Autodesk Fusion 360 part; units mm, degrees
(part 10 of 10)
equation "d2179 = abs(2 * panelWidth - mountInset)"
equation "d2180 = abs(2 * panelHeight - mountInset)"
equation "d2182 = hookClearance - seatThickness"
equation "d2184 = abs(2 * panelWidth - mountInset)"
equation "d2185 = abs(2 * panelHeight - mountInset)"
equation "d2186 = screwClearance"
equation "d2187 = frameZ"
equation "d2189 = -capThickness - 3 mm"
equation "d2191 = abs(2 * panelWidth - mountInset)"
equation "d2192 = abs(2 * panelHeight - mountInset)"
equation "d2196 = -capThickness"
equation "d2198 = abs(2 * panelWidth - mountInset)"
equation "d2199 = abs(2 * panelHeight - mountInset)"
equation "d2201 = frameZ + capThickness + 5 mm"
equation "d2203 = frameZ + profileLip"
equation "d2205 = abs(2 * panelWidth - mountInset - nutWidth / 2)"
equation "d2206 = abs(2 * panelHeight - mountInset - nutLength / 2)"
equation "d2207 = nutWidth"
equation "d2208 = nutLength"
equation "d2209 = nutThickness"
equation "d2211 = frameZ + profileLip"
equation "d2213 = abs(2 * panelWidth - mountInset)"
equation "d2214 = abs(2 * panelHeight - mountInset)"
equation "d2216 = nutThickness"
equation "d2218 = frameZ + 2 mm"
equation "d2220 = abs(( mountInset + 10 mm ))"
equation "d2221 = abs(( mountInset + 10 mm ))"
equation "d2222 = jointThickness"
equation "d2223 = jointLeg"
equation "d2224 = jointDepth"
equation "d2226 = frameZ + 2 mm"
equation "d2228 = abs(( mountInset + 10 mm ))"
equation "d2229 = abs(( mountInset + 10 mm ))"
equation "d2230 = jointLeg"
equation "d2231 = jointThickness"
equation "d2232 = jointDepth"
equation "d2234 = ( ( mountInset + 10 mm ) ) * 1.0"
equation "d2236 = abs(( frameZ + 10 mm ) * -1)"
equation "d2237 = abs(( ( mountInset + 10 mm ) + ( 1 ) * 12 mm ) * 1)"
equation "d2239 = ( 1 * jointThickness ) * 1.0"
equation "d2241 = ( ( mountInset + 10 mm ) ) * 1.0"
equation "d2243 = abs(( ( mountInset + 10 mm ) + ( 1 ) * 12 mm ) * 1)"
equation "d2244 = abs(( frameZ + 10 mm ) * -1)"
equation "d2246 = ( 1 * jointThickness ) * 1.0"
equation "d2248 = ( ( ( mountInset + 10 mm ) ) + ( 1 ) * jointThickness ) * 1.0"
equation "d2250 = abs(( frameZ + 10 mm ) * -1)"
equation "d2251 = abs(( ( mountInset + 10 mm ) + ( 1 ) * 12 mm ) * 1)"
equation "d2253 = ( ( 1 ) * 3 mm ) * 1.0"
equation "d2255 = ( ( ( mountInset + 10 mm ) ) + ( 1 ) * jointThickness ) * 1.0"
equation "d2257 = abs(( frameZ + 10 mm ) * -1)"
equation "d2258 = abs(( ( mountInset + 10 mm ) + ( 1 ) * 12 mm ) * 1)"
equation "d2260 = ( -( 1 ) * sideScrewLength ) * 1.0"
equation "d2262 = frameZ + 10 mm - nutWidth / 2"
equation "d2264 = abs(( ( mountInset + 10 mm ) ) - profileLip - nutThickness)"
equation "d2265 = abs(( mountInset + 10 mm ) + ( 1 ) * 12 mm - nutLength / 2)"
equation "d2266 = nutThickness"
equation "d2267 = nutLength"
equation "d2268 = nutWidth"
equation "d2270 = ( ( ( mountInset + 10 mm ) ) - profileLip - nutThickness ) * 1.0"
equation "d2272 = abs(( frameZ + 10 mm ) * -1)"
equation "d2273 = abs(( ( mountInset + 10 mm ) + ( 1 ) * 12 mm ) * 1)"
equation "d2275 = ( nutThickness ) * 1.0"
equation "d2277 = ( ( ( mountInset + 10 mm ) ) + ( 1 ) * jointThickness ) * 1.0"
equation "d2279 = abs(( ( mountInset + 10 mm ) + ( 1 ) * 12 mm ) * 1)"
equation "d2280 = abs(( frameZ + 10 mm ) * -1)"
equation "d2282 = ( ( 1 ) * 3 mm ) * 1.0"
equation "d2284 = ( ( ( mountInset + 10 mm ) ) + ( 1 ) * jointThickness ) * 1.0"
equation "d2286 = abs(( ( mountInset + 10 mm ) + ( 1 ) * 12 mm ) * 1)"
equation "d2287 = abs(( frameZ + 10 mm ) * -1)"
equation "d2289 = ( -( 1 ) * sideScrewLength ) * 1.0"
equation "d2291 = frameZ + 10 mm - nutWidth / 2"
equation "d2293 = abs(( mountInset + 10 mm ) + ( 1 ) * 12 mm - nutLength / 2)"
equation "d2294 = abs(( ( mountInset + 10 mm ) ) - profileLip - nutThickness)"
equation "d2295 = nutLength"
equation "d2296 = nutThickness"
equation "d2297 = nutWidth"
equation "d2299 = ( ( ( mountInset + 10 mm ) ) - profileLip - nutThickness ) * 1.0"
equation "d2301 = abs(( ( mountInset + 10 mm ) + ( 1 ) * 12 mm ) * 1)"
equation "d2302 = abs(( frameZ + 10 mm ) * -1)"
equation "d2304 = ( nutThickness ) * 1.0"
equation "d2306 = frameZ + 2 mm"
equation "d2308 = abs(( panelWidth - 10 mm ) - jointThickness)"
equation "d2309 = abs(( mountInset + 10 mm ))"
equation "d2310 = jointThickness"
equation "d2311 = jointLeg"
equation "d2312 = jointDepth"
equation "d2314 = frameZ + 2 mm"
equation "d2316 = abs(( panelWidth - 10 mm ) - jointLeg)"
equation "d2317 = abs(( mountInset + 10 mm ))"
equation "d2318 = jointLeg"
equation "d2319 = jointThickness"
equation "d2320 = jointDepth"
equation "d2322 = ( ( panelWidth - 10 mm ) ) * 1.0"
equation "d2324 = abs(( frameZ + 10 mm ) * -1)"
equation "d2325 = abs(( ( mountInset + 10 mm ) + ( 1 ) * 12 mm ) * 1)"
equation "d2327 = ( -1 * jointThickness ) * 1.0"
equation "d2329 = ( ( mountInset + 10 mm ) ) * 1.0"
equation "d2331 = abs(( ( panelWidth - 10 mm ) + ( -1 ) * 12 mm ) * 1)"
equation "d2332 = abs(( frameZ + 10 mm ) * -1)"
equation "d2334 = ( 1 * jointThickness ) * 1.0"
equation "d2336 = ( ( ( panelWidth - 10 mm ) ) + ( -1 ) * jointThickness ) * 1.0"
equation "d2338 = abs(( frameZ + 10 mm ) * -1)"
equation "d2339 = abs(( ( mountInset + 10 mm ) + ( 1 ) * 12 mm ) * 1)"
equation "d2341 = ( ( -1 ) * 3 mm ) * 1.0"
equation "d2343 = ( ( ( panelWidth - 10 mm ) ) + ( -1 ) * jointThickness ) * 1.0"
equation "d2345 = abs(( frameZ + 10 mm ) * -1)"
equation "d2346 = abs(( ( mountInset + 10 mm ) + ( 1 ) * 12 mm ) * 1)"
equation "d2348 = ( -( -1 ) * sideScrewLength ) * 1.0"
equation "d2350 = frameZ + 10 mm - nutWidth / 2"
equation "d2352 = abs(( ( panelWidth - 10 mm ) ) + profileLip)"
equation "d2353 = abs(( mountInset + 10 mm ) + ( 1 ) * 12 mm - nutLength / 2)"
equation "d2354 = nutThickness"
equation "d2355 = nutLength"
equation "d2356 = nutWidth"
equation "d2358 = ( ( ( panelWidth - 10 mm ) ) + profileLip ) * 1.0"
equation "d2360 = abs(( frameZ + 10 mm ) * -1)"
equation "d2361 = abs(( ( mountInset + 10 mm ) + ( 1 ) * 12 mm ) * 1)"
equation "d2363 = ( nutThickness ) * 1.0"
equation "d2365 = ( ( ( mountInset + 10 mm ) ) + ( 1 ) * jointThickness ) * 1.0"
equation "d2367 = abs(( ( panelWidth - 10 mm ) + ( -1 ) * 12 mm ) * 1)"
equation "d2368 = abs(( frameZ + 10 mm ) * -1)"
equation "d2370 = ( ( 1 ) * 3 mm ) * 1.0"
equation "d2372 = ( ( ( mountInset + 10 mm ) ) + ( 1 ) * jointThickness ) * 1.0"
equation "d2374 = abs(( ( panelWidth - 10 mm ) + ( -1 ) * 12 mm ) * 1)"
equation "d2375 = abs(( frameZ + 10 mm ) * -1)"
equation "d2377 = ( -( 1 ) * sideScrewLength ) * 1.0"
equation "d2379 = frameZ + 10 mm - nutWidth / 2"
equation "d2381 = abs(( panelWidth - 10 mm ) + ( -1 ) * 12 mm - nutLength / 2)"
equation "d2382 = abs(( ( mountInset + 10 mm ) ) - profileLip - nutThickness)"
equation "d2383 = nutLength"
equation "d2384 = nutThickness"
equation "d2385 = nutWidth"
equation "d2387 = ( ( ( mountInset + 10 mm ) ) - profileLip - nutThickness ) * 1.0"
equation "d2389 = abs(( ( panelWidth - 10 mm ) + ( -1 ) * 12 mm ) * 1)"
equation "d2390 = abs(( frameZ + 10 mm ) * -1)"
equation "d2392 = ( nutThickness ) * 1.0"
equation "d2394 = frameZ + 2 mm"
equation "d2396 = abs(( panelWidth + 10 mm ))"
equation "d2397 = abs(( mountInset + 10 mm ))"
equation "d2398 = jointThickness"
equation "d2399 = jointLeg"
equation "d2400 = jointDepth"
equation "d2402 = frameZ + 2 mm"
equation "d2404 = abs(( panelWidth + 10 mm ))"
equation "d2405 = abs(( mountInset + 10 mm ))"
equation "d2406 = jointLeg"
equation "d2407 = jointThickness"
equation "d2408 = jointDepth"
equation "d2410 = ( ( panelWidth + 10 mm ) ) * 1.0"
equation "d2412 = abs(( frameZ + 10 mm ) * -1)"
equation "d2413 = abs(( ( mountInset + 10 mm ) + ( 1 ) * 12 mm ) * 1)"
equation "d2415 = ( 1 * jointThickness ) * 1.0"
equation "d2417 = ( ( mountInset + 10 mm ) ) * 1.0"
equation "d2419 = abs(( ( panelWidth + 10 mm ) + ( 1 ) * 12 mm ) * 1)"
equation "d2420 = abs(( frameZ + 10 mm ) * -1)"
equation "d2422 = ( 1 * jointThickness ) * 1.0"
equation "d2424 = ( ( ( panelWidth + 10 mm ) ) + ( 1 ) * jointThickness ) * 1.0"
equation "d2426 = abs(( frameZ + 10 mm ) * -1)"
equation "d2427 = abs(( ( mountInset + 10 mm ) + ( 1 ) * 12 mm ) * 1)"
equation "d2429 = ( ( 1 ) * 3 mm ) * 1.0"
equation "d2431 = ( ( ( panelWidth + 10 mm ) ) + ( 1 ) * jointThickness ) * 1.0"
equation "d2433 = abs(( frameZ + 10 mm ) * -1)"
equation "d2434 = abs(( ( mountInset + 10 mm ) + ( 1 ) * 12 mm ) * 1)"
equation "d2436 = ( -( 1 ) * sideScrewLength ) * 1.0"
equation "d2438 = frameZ + 10 mm - nutWidth / 2"
equation "d2440 = abs(( ( panelWidth + 10 mm ) ) - profileLip - nutThickness)"
equation "d2441 = abs(( mountInset + 10 mm ) + ( 1 ) * 12 mm - nutLength / 2)"
equation "d2442 = nutThickness"
equation "d2443 = nutLength"
equation "d2444 = nutWidth"
equation "d2446 = ( ( ( panelWidth + 10 mm ) ) - profileLip - nutThickness ) * 1.0"
equation "d2448 = abs(( frameZ + 10 mm ) * -1)"
equation "d2449 = abs(( ( mountInset + 10 mm ) + ( 1 ) * 12 mm ) * 1)"
equation "d2451 = ( nutThickness ) * 1.0"
equation "d2453 = ( ( ( mountInset + 10 mm ) ) + ( 1 ) * jointThickness ) * 1.0"
equation "d2455 = abs(( ( panelWidth + 10 mm ) + ( 1 ) * 12 mm ) * 1)"
equation "d2456 = abs(( frameZ + 10 mm ) * -1)"
equation "d2458 = ( ( 1 ) * 3 mm ) * 1.0"
equation "d2460 = ( ( ( mountInset + 10 mm ) ) + ( 1 ) * jointThickness ) * 1.0"
equation "d2462 = abs(( ( panelWidth + 10 mm ) + ( 1 ) * 12 mm ) * 1)"
equation "d2463 = abs(( frameZ + 10 mm ) * -1)"
equation "d2465 = ( -( 1 ) * sideScrewLength ) * 1.0"
equation "d2467 = frameZ + 10 mm - nutWidth / 2"
equation "d2469 = abs(( panelWidth + 10 mm ) + ( 1 ) * 12 mm - nutLength / 2)"
equation "d2470 = abs(( ( mountInset + 10 mm ) ) - profileLip - nutThickness)"
equation "d2471 = nutLength"
equation "d2472 = nutThickness"
equation "d2473 = nutWidth"
equation "d2475 = ( ( ( mountInset + 10 mm ) ) - profileLip - nutThickness ) * 1.0"
equation "d2477 = abs(( ( panelWidth + 10 mm ) + ( 1 ) * 12 mm ) * 1)"
equation "d2478 = abs(( frameZ + 10 mm ) * -1)"
equation "d2480 = ( nutThickness ) * 1.0"
equation "d2482 = frameZ + 2 mm"
equation "d2484 = abs(( 2 * panelWidth - mountInset - 10 mm ) - jointThickness)"
equation "d2485 = abs(( mountInset + 10 mm ))"
equation "d2486 = jointThickness"
equation "d2487 = jointLeg"
equation "d2488 = jointDepth"
equation "d2490 = frameZ + 2 mm"
equation "d2492 = abs(( 2 * panelWidth - mountInset - 10 mm ) - jointLeg)"
equation "d2493 = abs(( mountInset + 10 mm ))"
equation "d2494 = jointLeg"
equation "d2495 = jointThickness"
equation "d2496 = jointDepth"
equation "d2498 = ( ( 2 * panelWidth - mountInset - 10 mm ) ) * 1.0"
equation "d2500 = abs(( frameZ + 10 mm ) * -1)"
equation "d2501 = abs(( ( mountInset + 10 mm ) + ( 1 ) * 12 mm ) * 1)"
equation "d2503 = ( -1 * jointThickness ) * 1.0"
equation "d2505 = ( ( mountInset + 10 mm ) ) * 1.0"
equation "d2507 = abs(( ( 2 * panelWidth - mountInset - 10 mm ) + ( -1 ) * 12 mm ) * 1)"
equation "d2508 = abs(( frameZ + 10 mm ) * -1)"
equation "d2510 = ( 1 * jointThickness ) * 1.0"
equation "d2512 = ( ( ( 2 * panelWidth - mountInset - 10 mm ) ) + ( -1 ) * jointThickness ) * 1.0"
equation "d2514 = abs(( frameZ + 10 mm ) * -1)"
equation "d2515 = abs(( ( mountInset + 10 mm ) + ( 1 ) * 12 mm ) * 1)"
equation "d2517 = ( ( -1 ) * 3 mm ) * 1.0"
equation "d2519 = ( ( ( 2 * panelWidth - mountInset - 10 mm ) ) + ( -1 ) * jointThickness ) * 1.0"
equation "d2521 = abs(( frameZ + 10 mm ) * -1)"
equation "d2522 = abs(( ( mountInset + 10 mm ) + ( 1 ) * 12 mm ) * 1)"
equation "d2524 = ( -( -1 ) * sideScrewLength ) * 1.0"
equation "d2526 = frameZ + 10 mm - nutWidth / 2"
equation "d2528 = abs(( ( 2 * panelWidth - mountInset - 10 mm ) ) + profileLip)"
equation "d2529 = abs(( mountInset + 10 mm ) + ( 1 ) * 12 mm - nutLength / 2)"
equation "d2530 = nutThickness"
equation "d2531 = nutLength"
equation "d2532 = nutWidth"
equation "d2534 = ( ( ( 2 * panelWidth - mountInset - 10 mm ) ) + profileLip ) * 1.0"
equation "d2536 = abs(( frameZ + 10 mm ) * -1)"
equation "d2537 = abs(( ( mountInset + 10 mm ) + ( 1 ) * 12 mm ) * 1)"
equation "d2539 = ( nutThickness ) * 1.0"
equation "d2541 = ( ( ( mountInset + 10 mm ) ) + ( 1 ) * jointThickness ) * 1.0"
equation "d2543 = abs(( ( 2 * panelWidth - mountInset - 10 mm ) + ( -1 ) * 12 mm ) * 1)"
equation "d2544 = abs(( frameZ + 10 mm ) * -1)"
equation "d2546 = ( ( 1 ) * 3 mm ) * 1.0"
equation "d2548 = ( ( ( mountInset + 10 mm ) ) + ( 1 ) * jointThickness ) * 1.0"
equation "d2550 = abs(( ( 2 * panelWidth - mountInset - 10 mm ) + ( -1 ) * 12 mm ) * 1)"
equation "d2551 = abs(( frameZ + 10 mm ) * -1)"
equation "d2553 = ( -( 1 ) * sideScrewLength ) * 1.0"
equation "d2555 = frameZ + 10 mm - nutWidth / 2"
equation "d2557 = abs(( 2 * panelWidth - mountInset - 10 mm ) + ( -1 ) * 12 mm - nutLength / 2)"
equation "d2558 = abs(( ( mountInset + 10 mm ) ) - profileLip - nutThickness)"
equation "d2559 = nutLength"
equation "d2560 = nutThickness"
equation "d2561 = nutWidth"
equation "d2563 = ( ( ( mountInset + 10 mm ) ) - profileLip - nutThickness ) * 1.0"
equation "d2565 = abs(( ( 2 * panelWidth - mountInset - 10 mm ) + ( -1 ) * 12 mm ) * 1)"
equation "d2566 = abs(( frameZ + 10 mm ) * -1)"
equation "d2568 = ( nutThickness ) * 1.0"
equation "d2570 = frameZ + 2 mm"
equation "d2572 = abs(( mountInset + 10 mm ))"
equation "d2573 = abs(( 2 * panelHeight - mountInset - 10 mm ) - jointLeg)"
equation "d2574 = jointThickness"
equation "d2575 = jointLeg"
equation "d2576 = jointDepth"
equation "d2578 = frameZ + 2 mm"
equation "d2580 = abs(( mountInset + 10 mm ))"
equation "d2581 = abs(( 2 * panelHeight - mountInset - 10 mm ) - jointThickness)"
equation "d2582 = jointLeg"
equation "d2583 = jointThickness"
equation "d2584 = jointDepth"
equation "d2586 = ( ( mountInset + 10 mm ) ) * 1.0"
equation "d2588 = abs(( frameZ + 10 mm ) * -1)"
equation "d2589 = abs(( ( 2 * panelHeight - mountInset - 10 mm ) + ( -1 ) * 12 mm ) * 1)"
equation "d2591 = ( 1 * jointThickness ) * 1.0"
equation "d2593 = ( ( 2 * panelHeight - mountInset - 10 mm ) ) * 1.0"
equation "d2595 = abs(( ( mountInset + 10 mm ) + ( 1 ) * 12 mm ) * 1)"
equation "d2596 = abs(( frameZ + 10 mm ) * -1)"
equation "d2598 = ( -1 * jointThickness ) * 1.0"
equation "d2600 = ( ( ( mountInset + 10 mm ) ) + ( 1 ) * jointThickness ) * 1.0"
equation "d2602 = abs(( frameZ + 10 mm ) * -1)"
equation "d2603 = abs(( ( 2 * panelHeight - mountInset - 10 mm ) + ( -1 ) * 12 mm ) * 1)"
equation "d2605 = ( ( 1 ) * 3 mm ) * 1.0"
equation "d2607 = ( ( ( mountInset + 10 mm ) ) + ( 1 ) * jointThickness ) * 1.0"
equation "d2609 = abs(( frameZ + 10 mm ) * -1)"
equation "d2610 = abs(( ( 2 * panelHeight - mountInset - 10 mm ) + ( -1 ) * 12 mm ) * 1)"
equation "d2612 = ( -( 1 ) * sideScrewLength ) * 1.0"
equation "d2614 = frameZ + 10 mm - nutWidth / 2"
equation "d2616 = abs(( ( mountInset + 10 mm ) ) - profileLip - nutThickness)"
equation "d2617 = abs(( 2 * panelHeight - mountInset - 10 mm ) + ( -1 ) * 12 mm - nutLength / 2)"
equation "d2618 = nutThickness"
equation "d2619 = nutLength"
equation "d2620 = nutWidth"
equation "d2622 = ( ( ( mountInset + 10 mm ) ) - profileLip - nutThickness ) * 1.0"
equation "d2624 = abs(( frameZ + 10 mm ) * -1)"
equation "d2625 = abs(( ( 2 * panelHeight - mountInset - 10 mm ) + ( -1 ) * 12 mm ) * 1)"
equation "d2627 = ( nutThickness ) * 1.0"
equation "d2629 = ( ( ( 2 * panelHeight - mountInset - 10 mm ) ) + ( -1 ) * jointThickness ) * 1.0"
equation "d2631 = abs(( ( mountInset + 10 mm ) + ( 1 ) * 12 mm ) * 1)"
equation "d2632 = abs(( frameZ + 10 mm ) * -1)"
equation "d2634 = ( ( -1 ) * 3 mm ) * 1.0"
equation "d2636 = ( ( ( 2 * panelHeight - mountInset - 10 mm ) ) + ( -1 ) * jointThickness ) * 1.0"
equation "d2638 = abs(( ( mountInset + 10 mm ) + ( 1 ) * 12 mm ) * 1)"
equation "d2639 = abs(( frameZ + 10 mm ) * -1)"
equation "d2641 = ( -( -1 ) * sideScrewLength ) * 1.0"
equation "d2643 = frameZ + 10 mm - nutWidth / 2"
equation "d2645 = abs(( mountInset + 10 mm ) + ( 1 ) * 12 mm - nutLength / 2)"
equation "d2646 = abs(( ( 2 * panelHeight - mountInset - 10 mm ) ) + profileLip)"
equation "d2647 = nutLength"
equation "d2648 = nutThickness"
equation "d2649 = nutWidth"
equation "d2651 = ( ( ( 2 * panelHeight - mountInset - 10 mm ) ) + profileLip ) * 1.0"
equation "d2653 = abs(( ( mountInset + 10 mm ) + ( 1 ) * 12 mm ) * 1)"
equation "d2654 = abs(( frameZ + 10 mm ) * -1)"
equation "d2656 = ( nutThickness ) * 1.0"
equation "d2658 = frameZ + 2 mm"
equation "d2660 = abs(( panelWidth - 10 mm ) - jointThickness)"
equation "d2661 = abs(( 2 * panelHeight - mountInset - 10 mm ) - jointLeg)"
equation "d2662 = jointThickness"
equation "d2663 = jointLeg"
equation "d2664 = jointDepth"
equation "d2666 = frameZ + 2 mm"
equation "d2668 = abs(( panelWidth - 10 mm ) - jointLeg)"
equation "d2669 = abs(( 2 * panelHeight - mountInset - 10 mm ) - jointThickness)"
equation "d2670 = jointLeg"
equation "d2671 = jointThickness"
equation "d2672 = jointDepth"
equation "d2674 = ( ( panelWidth - 10 mm ) ) * 1.0"
equation "d2676 = abs(( frameZ + 10 mm ) * -1)"
equation "d2677 = abs(( ( 2 * panelHeight - mountInset - 10 mm ) + ( -1 ) * 12 mm ) * 1)"
equation "d2679 = ( -1 * jointThickness ) * 1.0"
equation "d2681 = ( ( 2 * panelHeight - mountInset - 10 mm ) ) * 1.0"
equation "d2683 = abs(( ( panelWidth - 10 mm ) + ( -1 ) * 12 mm ) * 1)"
equation "d2684 = abs(( frameZ + 10 mm ) * -1)"
equation "d2686 = ( -1 * jointThickness ) * 1.0"
equation "d2688 = ( ( ( panelWidth - 10 mm ) ) + ( -1 ) * jointThickness ) * 1.0"
equation "d2690 = abs(( frameZ + 10 mm ) * -1)"
equation "d2691 = abs(( ( 2 * panelHeight - mountInset - 10 mm ) + ( -1 ) * 12 mm ) * 1)"
equation "d2693 = ( ( -1 ) * 3 mm ) * 1.0"
equation "d2695 = ( ( ( panelWidth - 10 mm ) ) + ( -1 ) * jointThickness ) * 1.0"
equation "d2697 = abs(( frameZ + 10 mm ) * -1)"
equation "d2698 = abs(( ( 2 * panelHeight - mountInset - 10 mm ) + ( -1 ) * 12 mm ) * 1)"
equation "d2700 = ( -( -1 ) * sideScrewLength ) * 1.0"
equation "d2702 = frameZ + 10 mm - nutWidth / 2"
equation "d2704 = abs(( ( panelWidth - 10 mm ) ) + profileLip)"
equation "d2705 = abs(( 2 * panelHeight - mountInset - 10 mm ) + ( -1 ) * 12 mm - nutLength / 2)"
equation "d2706 = nutThickness"
equation "d2707 = nutLength"
equation "d2708 = nutWidth"
equation "d2710 = ( ( ( panelWidth - 10 mm ) ) + profileLip ) * 1.0"
equation "d2712 = abs(( frameZ + 10 mm ) * -1)"
equation "d2713 = abs(( ( 2 * panelHeight - mountInset - 10 mm ) + ( -1 ) * 12 mm ) * 1)"
equation "d2715 = ( nutThickness ) * 1.0"
equation "d2717 = ( ( ( 2 * panelHeight - mountInset - 10 mm ) ) + ( -1 ) * jointThickness ) * 1.0"
equation "d2719 = abs(( ( panelWidth - 10 mm ) + ( -1 ) * 12 mm ) * 1)"
equation "d2720 = abs(( frameZ + 10 mm ) * -1)"
equation "d2722 = ( ( -1 ) * 3 mm ) * 1.0"
equation "d2724 = ( ( ( 2 * panelHeight - mountInset - 10 mm ) ) + ( -1 ) * jointThickness ) * 1.0"
equation "d2726 = abs(( ( panelWidth - 10 mm ) + ( -1 ) * 12 mm ) * 1)"
equation "d2727 = abs(( frameZ + 10 mm ) * -1)"
equation "d2729 = ( -( -1 ) * sideScrewLength ) * 1.0"
equation "d2731 = frameZ + 10 mm - nutWidth / 2"
equation "d2733 = abs(( panelWidth - 10 mm ) + ( -1 ) * 12 mm - nutLength / 2)"
equation "d2734 = abs(( ( 2 * panelHeight - mountInset - 10 mm ) ) + profileLip)"
equation "d2735 = nutLength"
equation "d2736 = nutThickness"
equation "d2737 = nutWidth"
equation "d2739 = ( ( ( 2 * panelHeight - mountInset - 10 mm ) ) + profileLip ) * 1.0"
equation "d2741 = abs(( ( panelWidth - 10 mm ) + ( -1 ) * 12 mm ) * 1)"
equation "d2742 = abs(( frameZ + 10 mm ) * -1)"
equation "d2744 = ( nutThickness ) * 1.0"
equation "d2746 = frameZ + 2 mm"
equation "d2748 = abs(( panelWidth + 10 mm ))"
equation "d2749 = abs(( 2 * panelHeight - mountInset - 10 mm ) - jointLeg)"
equation "d2750 = jointThickness"
equation "d2751 = jointLeg"
equation "d2752 = jointDepth"
equation "d2754 = frameZ + 2 mm"
equation "d2756 = abs(( panelWidth + 10 mm ))"
equation "d2757 = abs(( 2 * panelHeight - mountInset - 10 mm ) - jointThickness)"
equation "d2758 = jointLeg"
equation "d2759 = jointThickness"
equation "d2760 = jointDepth"
equation "d2762 = ( ( panelWidth + 10 mm ) ) * 1.0"
equation "d2764 = abs(( frameZ + 10 mm ) * -1)"
equation "d2765 = abs(( ( 2 * panelHeight - mountInset - 10 mm ) + ( -1 ) * 12 mm ) * 1)"
equation "d2767 = ( 1 * jointThickness ) * 1.0"
equation "d2769 = ( ( 2 * panelHeight - mountInset - 10 mm ) ) * 1.0"
equation "d2771 = abs(( ( panelWidth + 10 mm ) + ( 1 ) * 12 mm ) * 1)"
equation "d2772 = abs(( frameZ + 10 mm ) * -1)"
equation "d2774 = ( -1 * jointThickness ) * 1.0"
equation "d2776 = ( ( ( panelWidth + 10 mm ) ) + ( 1 ) * jointThickness ) * 1.0"
equation "d2778 = abs(( frameZ + 10 mm ) * -1)"
equation "d2779 = abs(( ( 2 * panelHeight - mountInset - 10 mm ) + ( -1 ) * 12 mm ) * 1)"
equation "d2781 = ( ( 1 ) * 3 mm ) * 1.0"
equation "d2783 = ( ( ( panelWidth + 10 mm ) ) + ( 1 ) * jointThickness ) * 1.0"
equation "d2785 = abs(( frameZ + 10 mm ) * -1)"
equation "d2786 = abs(( ( 2 * panelHeight - mountInset - 10 mm ) + ( -1 ) * 12 mm ) * 1)"
equation "d2788 = ( -( 1 ) * sideScrewLength ) * 1.0"
equation "d2790 = frameZ + 10 mm - nutWidth / 2"
equation "d2792 = abs(( ( panelWidth + 10 mm ) ) - profileLip - nutThickness)"
equation "d2793 = abs(( 2 * panelHeight - mountInset - 10 mm ) + ( -1 ) * 12 mm - nutLength / 2)"
equation "d2794 = nutThickness"
equation "d2795 = nutLength"
equation "d2796 = nutWidth"
equation "d2798 = ( ( ( panelWidth + 10 mm ) ) - profileLip - nutThickness ) * 1.0"
equation "d2800 = abs(( frameZ + 10 mm ) * -1)"
equation "d2801 = abs(( ( 2 * panelHeight - mountInset - 10 mm ) + ( -1 ) * 12 mm ) * 1)"
equation "d2803 = ( nutThickness ) * 1.0"
equation "d2805 = ( ( ( 2 * panelHeight - mountInset - 10 mm ) ) + ( -1 ) * jointThickness ) * 1.0"
equation "d2807 = abs(( ( panelWidth + 10 mm ) + ( 1 ) * 12 mm ) * 1)"
equation "d2808 = abs(( frameZ + 10 mm ) * -1)"
equation "d2810 = ( ( -1 ) * 3 mm ) * 1.0"
equation "d2812 = ( ( ( 2 * panelHeight - mountInset - 10 mm ) ) + ( -1 ) * jointThickness ) * 1.0"
equation "d2814 = abs(( ( panelWidth + 10 mm ) + ( 1 ) * 12 mm ) * 1)"
equation "d2815 = abs(( frameZ + 10 mm ) * -1)"
equation "d2817 = ( -( -1 ) * sideScrewLength ) * 1.0"
equation "d2819 = frameZ + 10 mm - nutWidth / 2"
equation "d2821 = abs(( panelWidth + 10 mm ) + ( 1 ) * 12 mm - nutLength / 2)"
equation "d2822 = abs(( ( 2 * panelHeight - mountInset - 10 mm ) ) + profileLip)"
equation "d2823 = nutLength"
equation "d2824 = nutThickness"
equation "d2825 = nutWidth"
equation "d2827 = ( ( ( 2 * panelHeight - mountInset - 10 mm ) ) + profileLip ) * 1.0"
equation "d2829 = abs(( ( panelWidth + 10 mm ) + ( 1 ) * 12 mm ) * 1)"
equation "d2830 = abs(( frameZ + 10 mm ) * -1)"
equation "d2832 = ( nutThickness ) * 1.0"
equation "d2834 = frameZ + 2 mm"
equation "d2836 = abs(( 2 * panelWidth - mountInset - 10 mm ) - jointThickness)"
equation "d2837 = abs(( 2 * panelHeight - mountInset - 10 mm ) - jointLeg)"
equation "d2838 = jointThickness"
equation "d2839 = jointLeg"
equation "d2840 = jointDepth"
equation "d2842 = frameZ + 2 mm"
equation "d2844 = abs(( 2 * panelWidth - mountInset - 10 mm ) - jointLeg)"
equation "d2845 = abs(( 2 * panelHeight - mountInset - 10 mm ) - jointThickness)"
equation "d2846 = jointLeg"
equation "d2847 = jointThickness"
equation "d2848 = jointDepth"
equation "d2850 = ( ( 2 * panelWidth - mountInset - 10 mm ) ) * 1.0"
equation "d2852 = abs(( frameZ + 10 mm ) * -1)"
equation "d2853 = abs(( ( 2 * panelHeight - mountInset - 10 mm ) + ( -1 ) * 12 mm ) * 1)"
equation "d2855 = ( -1 * jointThickness ) * 1.0"
equation "d2857 = ( ( 2 * panelHeight - mountInset - 10 mm ) ) * 1.0"
equation "d2859 = abs(( ( 2 * panelWidth - mountInset - 10 mm ) + ( -1 ) * 12 mm ) * 1)"
equation "d2860 = abs(( frameZ + 10 mm ) * -1)"
equation "d2862 = ( -1 * jointThickness ) * 1.0"
equation "d2864 = ( ( ( 2 * panelWidth - mountInset - 10 mm ) ) + ( -1 ) * jointThickness ) * 1.0"
equation "d2866 = abs(( frameZ + 10 mm ) * -1)"
equation "d2867 = abs(( ( 2 * panelHeight - mountInset - 10 mm ) + ( -1 ) * 12 mm ) * 1)"
equation "d2869 = ( ( -1 ) * 3 mm ) * 1.0"
equation "d2871 = ( ( ( 2 * panelWidth - mountInset - 10 mm ) ) + ( -1 ) * jointThickness ) * 1.0"
equation "d2873 = abs(( frameZ + 10 mm ) * -1)"
equation "d2874 = abs(( ( 2 * panelHeight - mountInset - 10 mm ) + ( -1 ) * 12 mm ) * 1)"
equation "d2876 = ( -( -1 ) * sideScrewLength ) * 1.0"
equation "d2878 = frameZ + 10 mm - nutWidth / 2"
equation "d2880 = abs(( ( 2 * panelWidth - mountInset - 10 mm ) ) + profileLip)"
equation "d2881 = abs(( 2 * panelHeight - mountInset - 10 mm ) + ( -1 ) * 12 mm - nutLength / 2)"
equation "d2882 = nutThickness"
equation "d2883 = nutLength"
equation "d2884 = nutWidth"
equation "d2886 = ( ( ( 2 * panelWidth - mountInset - 10 mm ) ) + profileLip ) * 1.0"
equation "d2888 = abs(( frameZ + 10 mm ) * -1)"
equation "d2889 = abs(( ( 2 * panelHeight - mountInset - 10 mm ) + ( -1 ) * 12 mm ) * 1)"
equation "d2891 = ( nutThickness ) * 1.0"
equation "d2893 = ( ( ( 2 * panelHeight - mountInset - 10 mm ) ) + ( -1 ) * jointThickness ) * 1.0"
equation "d2895 = abs(( ( 2 * panelWidth - mountInset - 10 mm ) + ( -1 ) * 12 mm ) * 1)"
equation "d2896 = abs(( frameZ + 10 mm ) * -1)"
equation "d2898 = ( ( -1 ) * 3 mm ) * 1.0"
equation "d2900 = ( ( ( 2 * panelHeight - mountInset - 10 mm ) ) + ( -1 ) * jointThickness ) * 1.0"
equation "d2902 = abs(( ( 2 * panelWidth - mountInset - 10 mm ) + ( -1 ) * 12 mm ) * 1)"
equation "d2903 = abs(( frameZ + 10 mm ) * -1)"
equation "d2905 = ( -( -1 ) * sideScrewLength ) * 1.0"
equation "d2907 = frameZ + 10 mm - nutWidth / 2"
equation "d2909 = abs(( 2 * panelWidth - mountInset - 10 mm ) + ( -1 ) * 12 mm - nutLength / 2)"
equation "d2910 = abs(( ( 2 * panelHeight - mountInset - 10 mm ) ) + profileLip)"
equation "d2911 = nutLength"
equation "d2912 = nutThickness"
equation "d2913 = nutWidth"
equation "d2915 = ( ( ( 2 * panelHeight - mountInset - 10 mm ) ) + profileLip ) * 1.0"
equation "d2917 = abs(( ( 2 * panelWidth - mountInset - 10 mm ) + ( -1 ) * 12 mm ) * 1)"
equation "d2918 = abs(( frameZ + 10 mm ) * -1)"
equation "d2920 = ( nutThickness ) * 1.0"
equation "d2922 = frameZ"
equation "d2924 = abs(( mountInset + 10 mm ))"
equation "d2925 = abs(2 * panelHeight / 3 - wallTabHeight / 2)"
equation "d2926 = jointThickness"
equation "d2927 = wallTabHeight"
equation "d2930 = frameZ + 20 mm - jointThickness"
equation "d2932 = abs(( mountInset + 10 mm ))"
equation "d2933 = abs(2 * panelHeight / 3 - wallTabHeight / 2)"
equation "d2934 = wallTabReach"
equation "d2935 = wallTabHeight"
equation "d2936 = jointThickness"
equation "d2938 = ( ( mountInset + 10 mm ) ) * 1.0"
equation "d2940 = abs(( frameZ + 10 mm ) * -1)"
equation "d2941 = abs(( 2 * panelHeight / 3 + ( -6 mm ) ) * 1)"
equation "d2943 = ( 1 * jointThickness ) * 1.0"
equation "d2945 = ( ( ( mountInset + 10 mm ) ) + ( 1 ) * jointThickness ) * 1.0"
equation "d2947 = abs(( frameZ + 10 mm ) * -1)"
equation "d2948 = abs(( 2 * panelHeight / 3 + ( -6 mm ) ) * 1)"
equation "d2950 = ( ( 1 ) * 3 mm ) * 1.0"
equation "d2952 = ( ( ( mountInset + 10 mm ) ) + ( 1 ) * jointThickness ) * 1.0"
equation "d2954 = abs(( frameZ + 10 mm ) * -1)"
equation "d2955 = abs(( 2 * panelHeight / 3 + ( -6 mm ) ) * 1)"
equation "d2957 = ( -( 1 ) * sideScrewLength ) * 1.0"
equation "d2959 = frameZ + 10 mm - nutWidth / 2"
equation "d2961 = abs(( ( mountInset + 10 mm ) ) - profileLip - nutThickness)"
equation "d2962 = abs(2 * panelHeight / 3 + ( -6 mm ) - nutLength / 2)"
equation "d2963 = nutThickness"
equation "d2964 = nutLength"
equation "d2965 = nutWidth"
equation "d2967 = ( ( ( mountInset + 10 mm ) ) - profileLip - nutThickness ) * 1.0"
equation "d2969 = abs(( frameZ + 10 mm ) * -1)"
equation "d2970 = abs(( 2 * panelHeight / 3 + ( -6 mm ) ) * 1)"
equation "d2972 = ( nutThickness ) * 1.0"
equation "d2974 = ( ( mountInset + 10 mm ) ) * 1.0"
equation "d2976 = abs(( frameZ + 10 mm ) * -1)"
equation "d2977 = abs(( 2 * panelHeight / 3 + ( 6 mm ) ) * 1)"
equation "d2979 = ( 1 * jointThickness ) * 1.0"
equation "d2981 = ( ( ( mountInset + 10 mm ) ) + ( 1 ) * jointThickness ) * 1.0"
equation "d2983 = abs(( frameZ + 10 mm ) * -1)"
equation "d2984 = abs(( 2 * panelHeight / 3 + ( 6 mm ) ) * 1)"
equation "d2986 = ( ( 1 ) * 3 mm ) * 1.0"
equation "d2988 = ( ( ( mountInset + 10 mm ) ) + ( 1 ) * jointThickness ) * 1.0"
equation "d2990 = abs(( frameZ + 10 mm ) * -1)"
equation "d2991 = abs(( 2 * panelHeight / 3 + ( 6 mm ) ) * 1)"
equation "d2993 = ( -( 1 ) * sideScrewLength ) * 1.0"
equation "d2995 = frameZ + 10 mm - nutWidth / 2"
equation "d2997 = abs(( ( mountInset + 10 mm ) ) - profileLip - nutThickness)"
equation "d2998 = abs(2 * panelHeight / 3 + ( 6 mm ) - nutLength / 2)"
equation "d2999 = nutThickness"
equation "d3000 = nutLength"
equation "d3001 = nutWidth"
equation "d3003 = ( ( ( mountInset + 10 mm ) ) - profileLip - nutThickness ) * 1.0"
equation "d3005 = abs(( frameZ + 10 mm ) * -1)"
equation "d3006 = abs(( 2 * panelHeight / 3 + ( 6 mm ) ) * 1)"
equation "d3008 = ( nutThickness ) * 1.0"
equation "d3010 = frameZ + 20 mm - jointThickness"
equation "d3012 = abs(( mountInset + 10 mm ) + ( 1 ) * 13 mm)"
equation "d3013 = abs(2 * panelHeight / 3)"
equation "d3014 = wallAnchorClearance"
equation "d3015 = jointThickness"
equation "d3017 = frameZ + 20 mm - jointThickness - 3 mm"
equation "d3019 = abs(( mountInset + 10 mm ) + ( 1 ) * 13 mm)"
equation "d3020 = abs(2 * panelHeight / 3)"
equation "d3024 = frameZ + 20 mm - jointThickness"
equation "d3026 = abs(( mountInset + 10 mm ) + ( 1 ) * 13 mm)"
equation "d3027 = abs(2 * panelHeight / 3)"
equation "d3029 = jointThickness"
equation "d3031 = frameZ"
equation "d3033 = abs(( mountInset + 10 mm ))"
equation "d3034 = abs(4 * panelHeight / 3 - wallTabHeight / 2)"
equation "d3035 = jointThickness"
equation "d3036 = wallTabHeight"
equation "d3039 = frameZ + 20 mm - jointThickness"
equation "d3041 = abs(( mountInset + 10 mm ))"
equation "d3042 = abs(4 * panelHeight / 3 - wallTabHeight / 2)"
equation "d3043 = wallTabReach"
equation "d3044 = wallTabHeight"
equation "d3045 = jointThickness"
equation "d3047 = ( ( mountInset + 10 mm ) ) * 1.0"
equation "d3049 = abs(( frameZ + 10 mm ) * -1)"
equation "d3050 = abs(( 4 * panelHeight / 3 + ( -6 mm ) ) * 1)"
equation "d3052 = ( 1 * jointThickness ) * 1.0"
equation "d3054 = ( ( ( mountInset + 10 mm ) ) + ( 1 ) * jointThickness ) * 1.0"
equation "d3056 = abs(( frameZ + 10 mm ) * -1)"
equation "d3057 = abs(( 4 * panelHeight / 3 + ( -6 mm ) ) * 1)"
equation "d3059 = ( ( 1 ) * 3 mm ) * 1.0"
equation "d3061 = ( ( ( mountInset + 10 mm ) ) + ( 1 ) * jointThickness ) * 1.0"
equation "d3063 = abs(( frameZ + 10 mm ) * -1)"
equation "d3064 = abs(( 4 * panelHeight / 3 + ( -6 mm ) ) * 1)"
equation "d3066 = ( -( 1 ) * sideScrewLength ) * 1.0"
equation "d3068 = frameZ + 10 mm - nutWidth / 2"
equation "d3070 = abs(( ( mountInset + 10 mm ) ) - profileLip - nutThickness)"
equation "d3071 = abs(4 * panelHeight / 3 + ( -6 mm ) - nutLength / 2)"
equation "d3072 = nutThickness"
equation "d3073 = nutLength"
equation "d3074 = nutWidth"
equation "d3076 = ( ( ( mountInset + 10 mm ) ) - profileLip - nutThickness ) * 1.0"
equation "d3078 = abs(( frameZ + 10 mm ) * -1)"
equation "d3079 = abs(( 4 * panelHeight / 3 + ( -6 mm ) ) * 1)"
equation "d3081 = ( nutThickness ) * 1.0"
equation "d3083 = ( ( mountInset + 10 mm ) ) * 1.0"
equation "d3085 = abs(( frameZ + 10 mm ) * -1)"
equation "d3086 = abs(( 4 * panelHeight / 3 + ( 6 mm ) ) * 1)"
equation "d3088 = ( 1 * jointThickness ) * 1.0"
equation "d3090 = ( ( ( mountInset + 10 mm ) ) + ( 1 ) * jointThickness ) * 1.0"
equation "d3092 = abs(( frameZ + 10 mm ) * -1)"
equation "d3093 = abs(( 4 * panelHeight / 3 + ( 6 mm ) ) * 1)"
equation "d3095 = ( ( 1 ) * 3 mm ) * 1.0"
equation "d3097 = ( ( ( mountInset + 10 mm ) ) + ( 1 ) * jointThickness ) * 1.0"
equation "d3099 = abs(( frameZ + 10 mm ) * -1)"
equation "d3100 = abs(( 4 * panelHeight / 3 + ( 6 mm ) ) * 1)"
equation "d3102 = ( -( 1 ) * sideScrewLength ) * 1.0"
equation "d3104 = frameZ + 10 mm - nutWidth / 2"
equation "d3106 = abs(( ( mountInset + 10 mm ) ) - profileLip - nutThickness)"
equation "d3107 = abs(4 * panelHeight / 3 + ( 6 mm ) - nutLength / 2)"
equation "d3108 = nutThickness"
equation "d3109 = nutLength"
equation "d3110 = nutWidth"
equation "d3112 = ( ( ( mountInset + 10 mm ) ) - profileLip - nutThickness ) * 1.0"
equation "d3114 = abs(( frameZ + 10 mm ) * -1)"
equation "d3115 = abs(( 4 * panelHeight / 3 + ( 6 mm ) ) * 1)"
equation "d3117 = ( nutThickness ) * 1.0"
equation "d3119 = frameZ + 20 mm - jointThickness"
equation "d3121 = abs(( mountInset + 10 mm ) + ( 1 ) * 13 mm)"
equation "d3122 = abs(4 * panelHeight / 3)"
equation "d3123 = wallAnchorClearance"
equation "d3124 = jointThickness"
equation "d3126 = frameZ + 20 mm - jointThickness - 3 mm"
equation "d3128 = abs(( mountInset + 10 mm ) + ( 1 ) * 13 mm)"
equation "d3129 = abs(4 * panelHeight / 3)"
equation "d3133 = frameZ + 20 mm - jointThickness"
equation "d3135 = abs(( mountInset + 10 mm ) + ( 1 ) * 13 mm)"
equation "d3136 = abs(4 * panelHeight / 3)"
equation "d3138 = jointThickness"
equation "d3140 = frameZ"
equation "d3142 = abs(( 2 * panelWidth - mountInset - 10 mm ) - jointThickness)"
equation "d3143 = abs(2 * panelHeight / 3 - wallTabHeight / 2)"
equation "d3144 = jointThickness"
equation "d3145 = wallTabHeight"
equation "d3148 = frameZ + 20 mm - jointThickness"
equation "d3150 = abs(( 2 * panelWidth - mountInset - 10 mm ) - wallTabReach)"
equation "d3151 = abs(2 * panelHeight / 3 - wallTabHeight / 2)"
equation "d3152 = wallTabReach"
equation "d3153 = wallTabHeight"
equation "d3154 = jointThickness"
equation "d3156 = ( ( 2 * panelWidth - mountInset - 10 mm ) ) * 1.0"
equation "d3158 = abs(( frameZ + 10 mm ) * -1)"
equation "d3159 = abs(( 2 * panelHeight / 3 + ( -6 mm ) ) * 1)"
equation "d3161 = ( -1 * jointThickness ) * 1.0"
equation "d3163 = ( ( ( 2 * panelWidth - mountInset - 10 mm ) ) + ( -1 ) * jointThickness ) * 1.0"
equation "d3165 = abs(( frameZ + 10 mm ) * -1)"
equation "d3166 = abs(( 2 * panelHeight / 3 + ( -6 mm ) ) * 1)"
equation "d3168 = ( ( -1 ) * 3 mm ) * 1.0"
equation "d3170 = ( ( ( 2 * panelWidth - mountInset - 10 mm ) ) + ( -1 ) * jointThickness ) * 1.0"
equation "d3172 = abs(( frameZ + 10 mm ) * -1)"
equation "d3173 = abs(( 2 * panelHeight / 3 + ( -6 mm ) ) * 1)"
equation "d3175 = ( -( -1 ) * sideScrewLength ) * 1.0"
equation "d3177 = frameZ + 10 mm - nutWidth / 2"
equation "d3179 = abs(( ( 2 * panelWidth - mountInset - 10 mm ) ) + profileLip)"
equation "d3180 = abs(2 * panelHeight / 3 + ( -6 mm ) - nutLength / 2)"
equation "d3181 = nutThickness"
equation "d3182 = nutLength"
equation "d3183 = nutWidth"
equation "d3185 = ( ( ( 2 * panelWidth - mountInset - 10 mm ) ) + profileLip ) * 1.0"
equation "d3187 = abs(( frameZ + 10 mm ) * -1)"
equation "d3188 = abs(( 2 * panelHeight / 3 + ( -6 mm ) ) * 1)"
equation "d3190 = ( nutThickness ) * 1.0"
equation "d3192 = ( ( 2 * panelWidth - mountInset - 10 mm ) ) * 1.0"
equation "d3194 = abs(( frameZ + 10 mm ) * -1)"
equation "d3195 = abs(( 2 * panelHeight / 3 + ( 6 mm ) ) * 1)"
equation "d3197 = ( -1 * jointThickness ) * 1.0"
equation "d3199 = ( ( ( 2 * panelWidth - mountInset - 10 mm ) ) + ( -1 ) * jointThickness ) * 1.0"
equation "d3201 = abs(( frameZ + 10 mm ) * -1)"
equation "d3202 = abs(( 2 * panelHeight / 3 + ( 6 mm ) ) * 1)"
equation "d3204 = ( ( -1 ) * 3 mm ) * 1.0"
equation "d3206 = ( ( ( 2 * panelWidth - mountInset - 10 mm ) ) + ( -1 ) * jointThickness ) * 1.0"
equation "d3208 = abs(( frameZ + 10 mm ) * -1)"
equation "d3209 = abs(( 2 * panelHeight / 3 + ( 6 mm ) ) * 1)"
equation "d3211 = ( -( -1 ) * sideScrewLength ) * 1.0"
equation "d3213 = frameZ + 10 mm - nutWidth / 2"
equation "d3215 = abs(( ( 2 * panelWidth - mountInset - 10 mm ) ) + profileLip)"
equation "d3216 = abs(2 * panelHeight / 3 + ( 6 mm ) - nutLength / 2)"
equation "d3217 = nutThickness"
equation "d3218 = nutLength"
equation "d3219 = nutWidth"
equation "d3221 = ( ( ( 2 * panelWidth - mountInset - 10 mm ) ) + profileLip ) * 1.0"
equation "d3223 = abs(( frameZ + 10 mm ) * -1)"
equation "d3224 = abs(( 2 * panelHeight / 3 + ( 6 mm ) ) * 1)"
equation "d3226 = ( nutThickness ) * 1.0"
equation "d3228 = frameZ + 20 mm - jointThickness"
equation "d3230 = abs(( 2 * panelWidth - mountInset - 10 mm ) + ( -1 ) * 13 mm)"
equation "d3231 = abs(2 * panelHeight / 3)"
equation "d3232 = wallAnchorClearance"
equation "d3233 = jointThickness"
equation "d3235 = frameZ + 20 mm - jointThickness - 3 mm"
equation "d3237 = abs(( 2 * panelWidth - mountInset - 10 mm ) + ( -1 ) * 13 mm)"
equation "d3238 = abs(2 * panelHeight / 3)"
equation "d3242 = frameZ + 20 mm - jointThickness"
equation "d3244 = abs(( 2 * panelWidth - mountInset - 10 mm ) + ( -1 ) * 13 mm)"
equation "d3245 = abs(2 * panelHeight / 3)"
equation "d3247 = jointThickness"
equation "d3249 = frameZ"
equation "d3251 = abs(( 2 * panelWidth - mountInset - 10 mm ) - jointThickness)"
equation "d3252 = abs(4 * panelHeight / 3 - wallTabHeight / 2)"
equation "d3253 = jointThickness"
equation "d3254 = wallTabHeight"
equation "d3257 = frameZ + 20 mm - jointThickness"
equation "d3259 = abs(( 2 * panelWidth - mountInset - 10 mm ) - wallTabReach)"
equation "d3260 = abs(4 * panelHeight / 3 - wallTabHeight / 2)"
equation "d3261 = wallTabReach"
equation "d3262 = wallTabHeight"
equation "d3263 = jointThickness"
equation "d3265 = ( ( 2 * panelWidth - mountInset - 10 mm ) ) * 1.0"
equation "d3267 = abs(( frameZ + 10 mm ) * -1)"
equation "d3268 = abs(( 4 * panelHeight / 3 + ( -6 mm ) ) * 1)"
equation "d3270 = ( -1 * jointThickness ) * 1.0"
equation "d3272 = ( ( ( 2 * panelWidth - mountInset - 10 mm ) ) + ( -1 ) * jointThickness ) * 1.0"
equation "d3274 = abs(( frameZ + 10 mm ) * -1)"
equation "d3275 = abs(( 4 * panelHeight / 3 + ( -6 mm ) ) * 1)"
equation "d3277 = ( ( -1 ) * 3 mm ) * 1.0"
equation "d3279 = ( ( ( 2 * panelWidth - mountInset - 10 mm ) ) + ( -1 ) * jointThickness ) * 1.0"
equation "d3281 = abs(( frameZ + 10 mm ) * -1)"
equation "d3282 = abs(( 4 * panelHeight / 3 + ( -6 mm ) ) * 1)"
equation "d3284 = ( -( -1 ) * sideScrewLength ) * 1.0"
equation "d3286 = frameZ + 10 mm - nutWidth / 2"
equation "d3288 = abs(( ( 2 * panelWidth - mountInset - 10 mm ) ) + profileLip)"
equation "d3289 = abs(4 * panelHeight / 3 + ( -6 mm ) - nutLength / 2)"
equation "d3290 = nutThickness"
equation "d3291 = nutLength"
equation "d3292 = nutWidth"
equation "d3294 = ( ( ( 2 * panelWidth - mountInset - 10 mm ) ) + profileLip ) * 1.0"
equation "d3296 = abs(( frameZ + 10 mm ) * -1)"
equation "d3297 = abs(( 4 * panelHeight / 3 + ( -6 mm ) ) * 1)"
equation "d3299 = ( nutThickness ) * 1.0"
equation "d3301 = ( ( 2 * panelWidth - mountInset - 10 mm ) ) * 1.0"
equation "d3303 = abs(( frameZ + 10 mm ) * -1)"
equation "d3304 = abs(( 4 * panelHeight / 3 + ( 6 mm ) ) * 1)"
equation "d3306 = ( -1 * jointThickness ) * 1.0"
equation "d3308 = ( ( ( 2 * panelWidth - mountInset - 10 mm ) ) + ( -1 ) * jointThickness ) * 1.0"
equation "d3310 = abs(( frameZ + 10 mm ) * -1)"
equation "d3311 = abs(( 4 * panelHeight / 3 + ( 6 mm ) ) * 1)"
equation "d3313 = ( ( -1 ) * 3 mm ) * 1.0"
equation "d3315 = ( ( ( 2 * panelWidth - mountInset - 10 mm ) ) + ( -1 ) * jointThickness ) * 1.0"
equation "d3317 = abs(( frameZ + 10 mm ) * -1)"
equation "d3318 = abs(( 4 * panelHeight / 3 + ( 6 mm ) ) * 1)"
equation "d3320 = ( -( -1 ) * sideScrewLength ) * 1.0"
equation "d3322 = frameZ + 10 mm - nutWidth / 2"
equation "d3324 = abs(( ( 2 * panelWidth - mountInset - 10 mm ) ) + profileLip)"
equation "d3325 = abs(4 * panelHeight / 3 + ( 6 mm ) - nutLength / 2)"
equation "d3326 = nutThickness"
equation "d3327 = nutLength"
equation "d3328 = nutWidth"
equation "d3330 = ( ( ( 2 * panelWidth - mountInset - 10 mm ) ) + profileLip ) * 1.0"
equation "d3332 = abs(( frameZ + 10 mm ) * -1)"
equation "d3333 = abs(( 4 * panelHeight / 3 + ( 6 mm ) ) * 1)"
equation "d3335 = ( nutThickness ) * 1.0"
equation "d3337 = frameZ + 20 mm - jointThickness"
equation "d3339 = abs(( 2 * panelWidth - mountInset - 10 mm ) + ( -1 ) * 13 mm)"
equation "d3340 = abs(4 * panelHeight / 3)"
equation "d3341 = wallAnchorClearance"
equation "d3342 = jointThickness"
equation "d3344 = frameZ + 20 mm - jointThickness - 3 mm"
equation "d3346 = abs(( 2 * panelWidth - mountInset - 10 mm ) + ( -1 ) * 13 mm)"
equation "d3347 = abs(4 * panelHeight / 3)"
equation "d3351 = frameZ + 20 mm - jointThickness"
equation "d3353 = abs(( 2 * panelWidth - mountInset - 10 mm ) + ( -1 ) * 13 mm)"
equation "d3354 = abs(4 * panelHeight / 3)"
equation "d3356 = jointThickness"
named bodies: "Panel lower left", "Panel lower right", "Panel upper left", "Panel upper right"
